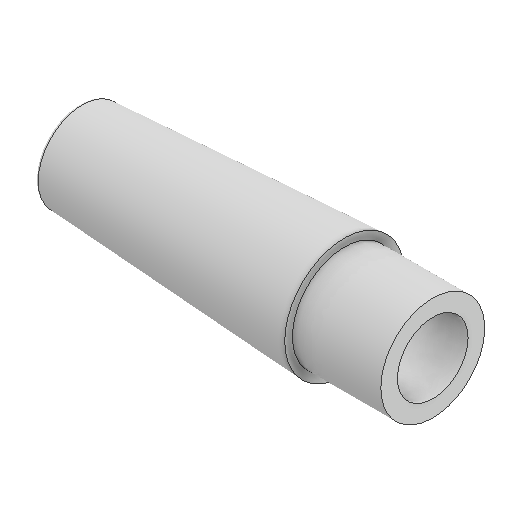
# Autodesk Inventor part: 3DP_PLA_B_Axis_Cable_Galnd
Saved by Autodesk Inventor 2027 (Build 310192060, 192F)
## iProperties
Created: 2026-01-18
Part Number: 3DP_PLA_B_Axis_Cable_Galnd
Material: Generic
Document SubType Name: Modeling
Designer: Andrzej
Density: 1 g/cm^3
Appearance: Default
Author: Andrzej
Autodesk Inventor part; units mm, degrees
ref_plane "YZ Plane" through (0, 0, 0) normal (1, 0, 0) x (0, 1, 0)
ref_plane "XZ Plane" through (0, 0, 0) normal (0, 1, 0) x (-1, 0, 0)
ref_plane "XY Plane" through (0, 0, 0) normal (0, 0, 1) x (1, 0, 0)
sketch "Sketch1" plane through (0, 0, 0) normal (0, 1, 0) x (-1, 0, 0)
  line L0 (-20, 8) -> (60, 8)
  line L1 (60, 8) -> (60, 10)
  line L2 (60, 10) -> (0, 13.5)
  line L3 (0, 13.5) -> (0, 11.75)
  line L4 (0, 11.75) -> (-20, 11.75)
  line L5 (-20, 11.75) -> (-20, 8)
  line L6 (76, 0) -> (-36, 0) projected
  point P0 (0, 0)
  dimension "d0" = 8
  dimension "d1" = 11.75
  dimension "d2" = 13.5
  dimension "d3" = 60
  dimension "d4" = 20
  dimension "d6" = 2
  constraints: 12 end point, 3 perpendicular, 1 horizontal, 1 parallel
  measures "d0" distance from line of point (0, 0) L0
  measures "d1" distance from line of point (0, 0) L4
  measures "d2" distance of point (0, 0) L2.end
  measures "d3" distance between parallel lines of L1 L3
  measures "d4" distance from line of point (0, 0) L5
  measures "d6" distance of L0.end L1.end
revolve "Revolution1" add sketch "Sketch1" angle 360 about axis through (-10, 0, 0) along (1, 0, 0)
fillet "Fillet1" radius 0.8 2 edges at (-60, 0, -10) (-60, 0, -8)
body "Solid1"
